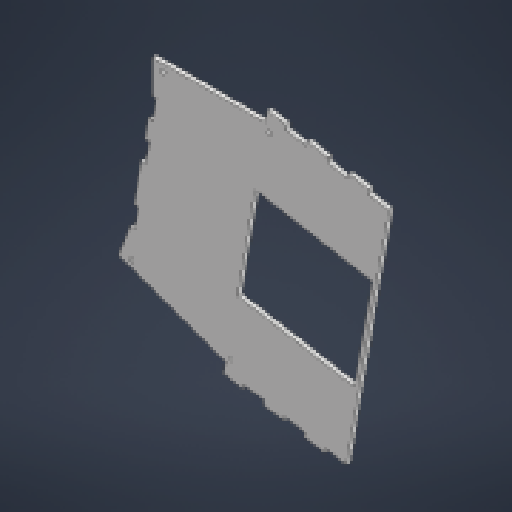
# Autodesk Inventor part: tapaderalateral
Saved by Autodesk Inventor 2027.1 (Build 311270010, 270A)
## iProperties
Created: 2026-10-11
Part Number: tapaderalateral
Material: Generic
Document SubType Name: Modeling
Designer: MineS
Density: 1 g/cm^3
Appearance: Default
Author: MineS
Autodesk Inventor part; units mm, degrees
ref_plane "YZ Plane" through (0, 0, 0) normal (1, 0, 0) x (0, 1, 0)
ref_plane "XZ Plane" through (0, 0, 0) normal (0, 1, 0) x (-1, 0, 0)
ref_plane "XY Plane" through (0, 0, 0) normal (0, 0, 1) x (1, 0, 0)
sketch "Sketch1" plane through (0, 0, 0) normal (0, 0, 1) x (1, 0, 0)
  line L0 (0, 0) -> (0, 24)
  line L1 (0, 24) -> (81.3777, 24)
  line L2 (81.3777, 24) -> (82.8537, 32.3709)
  line L3 (82.8537, 32.3709) -> (170.5618, 16.9056)
  line L4 (0, 0) -> (-15.6283, -88.6327)
  line L5 (-7.8142, -44.3163) -> (90.8416, -61.712)
  line L6 (90.8416, -61.712) -> (154.7135, -72.9744)
  line L7 (154.7135, -72.9744) -> (170.5618, 16.9056)
  line L8 (-15.6283, -88.6327) -> (-23.8368, -111.1853)
  line L9 (-23.8368, -111.1853) -> (52.6332, -139.0181)
  line L10 (52.6332, -139.0181) -> (51.1572, -147.389)
  line L11 (51.1572, -147.389) -> (138.8653, -162.8543)
  line L12 (154.7135, -72.9744) -> (138.8653, -162.8543)
  dimension "d1" = 24
  dimension "d2" = 100
  dimension "d3" = 90
  dimension "d25" = 8.5
  constraints: 26 end point, 4 symmetric about line, 3 perpendicular, 1 horizontal, 1 midpoint, 1 parallel, 1 vertical
  measures "d1" distance of L0.start L0.end
  measures "d2" angle of L1 L2
  measures "d3" distance of L0.start L4.end
  measures "d25" distance of L1.end L2.end
extrude "Extrusion1" add sketch "Sketch1" along normal blind 3.125
sketch "Sketch2" plane through (0, 0, 3.125) normal (0, 0, 1) x (1, 0, 0)
  circle A0 centre (8, 19) radius 1.45 projected
  circle A1 centre (84, 19) radius 1.45 projected
  line L0 (0, 0) -> (-15.6283, -88.6327) projected
  line L1 (-7.8142, -44.3163) -> (154.7135, -72.9744)
  line L2 (138.8653, -162.8543) -> (170.5618, 16.9056) projected
  circle A2 centre (-14.6092, -109.223) radius 1.45
  circle A3 centre (56.8075, -135.2165) radius 1.45
  circle A4 centre (8, 19) radius 1.5
  circle A5 centre (84, 19) radius 1.5
  circle A6 centre (56.8075, -135.2165) radius 1.5
  circle A7 centre (-14.6092, -109.223) radius 1.5
  dimension "d8" = 3
  dimension "d9" = 3
  dimension "d10" = 3
  dimension "d11" = 3
  constraints: 6 centre point, 4 coincident, 2 end point, 2 midpoint, 2 symmetric about line, 2 other
  measures "d8" diameter of A4
  measures "d9" diameter of A5
  measures "d10" diameter of A6
  measures "d11" diameter of A7
extrude "Extrusion3" cut sketch "Sketch2" against normal blind 3.125 contours A0 | A1 | A2 | A3 | A4 | A5 | A6 | A7
sketch "Sketch3" plane through (0, 0, 0) normal (0, 0, -1) x (-1, 0, 0)
  line L0 (-170.5618, 16.9056) -> (-82.8537, 32.3709) projected
  line L1 (-82.8537, 32.3709) -> (-82.3111, 29.2933)
  line L2 (-82.8537, 32.3709) -> (-81.3777, 24) projected
  line L3 (-82.3111, 29.2933) -> (-170.0192, 13.828)
  line L4 (-138.8653, -162.8543) -> (-170.5618, 16.9056) projected
  line L5 (-155.7897, 19.5103) -> (-155.247, 16.4328)
  line L6 (-141.0176, 22.115) -> (-140.4749, 19.0375)
  line L7 (-126.2455, 24.7197) -> (-125.7028, 21.6422)
  line L8 (-111.4733, 27.3245) -> (-110.9307, 24.2469)
  line L9 (-96.7012, 29.9292) -> (-96.1586, 26.8517)
  line L10 (0, 0) -> (15.6283, -88.6327) projected
  line L11 (7.8142, -44.3163) -> (-154.7135, -72.9744)
  line L12 (-138.8653, -162.8543) -> (-51.1572, -147.389)
  line L13 (-51.1572, -147.389) -> (-51.6999, -144.3115)
  line L14 (-51.1572, -147.389) -> (-52.6332, -139.0181)
  line L15 (-51.6999, -144.3115) -> (-139.4079, -159.7768)
  line L16 (-124.0932, -160.2496) -> (-124.6358, -157.1721)
  line L17 (-109.3211, -157.6449) -> (-109.8637, -154.5673)
  line L18 (-94.5489, -155.0401) -> (-95.0916, -151.9626)
  line L19 (-79.7768, -152.4354) -> (-80.3195, -149.3579)
  line L20 (-65.0047, -149.8307) -> (-65.5474, -146.7532)
  point P0 (-125.7028, 21.6422)
  point P1 (-126.2455, 24.7197)
  point P2 (-141.0176, 22.115)
  point P3 (-140.4749, 19.0375)
  point P4 (-96.7012, 29.9292)
  point P5 (-111.4733, 27.3245)
  point P6 (-110.9307, 24.2469)
  point P7 (-139.4079, -159.7768)
  point P8 (-109.3211, -157.6449)
  point P9 (-94.5489, -155.0401)
  point P10 (-65.5474, -146.7532)
  point P11 (-80.3195, -149.3579)
  point P12 (-79.7768, -152.4354)
  dimension "d14" = 3.125
  dimension "d15" = 15
  dimension "d18" = 15
  constraints: 34 end point, 14 symmetric about line, 7 point on line, 2 midpoint, 2 perpendicular, 13 other
  measures "d14" distance of L0.end L1.end
  measures "d15" distance between parallel lines of L4 L5
  measures "d18" distance of L5.start L6.start
extrude "Extrusion4" cut sketch "Sketch3" against normal blind 3.125 contours L15 L16 L12 L4 | L0 L5 L3 L4 | L0 L7 L3 L6 | L0 L9 L3 L8 | L15 L18 L12 L17 | L15 L20 L12 L19
sketch "Sketch4" plane through (0, 0, 3.125) normal (0, 0, 1) x (1, 0, 0)
  line L0 (139.4079, -159.7768) -> (170.0192, 13.828) projected
  line L1 (148.3754, -108.9199) -> (61.3922, -93.5824)
  line L2 (139.4079, -159.7768) -> (170.0192, 13.828) projected
  line L3 (61.3922, -93.5824) -> (74.0686, -21.6914)
  line L4 (0, 0) -> (-15.6283, -88.6327) projected
  line L5 (-7.8142, -44.3163) -> (154.7135, -72.9744)
  line L6 (74.0686, -21.6914) -> (161.0517, -37.0289)
  line L7 (145.2979, -108.3772) -> (157.9742, -36.4862)
  point P0 (67.7304, -57.6369)
  dimension "d26" = 88.325
  dimension "d27" = 73
  dimension "d28" = 3.125
  constraints: 10 end point, 5 point on line, 4 perpendicular, 3 midpoint
  measures "d26" distance of L1.start L1.end
  measures "d27" distance of L1.end L3.end
  measures "d28" distance between parallel lines of L0 L7
extrude "Extrusion5" cut sketch "Sketch4" against normal blind 10 contours L1 L3 L5 L7 | L5 L3 L6 L7
sketch "Sketch5" plane through (0, 0, 0) normal (0, 0, -1) x (-1, 0, 0)
  line L0 (0, 0) -> (15.6283, -88.6327) projected
  line L1 (0, 24) -> (0, 0) projected
  line L2 (15.6283, -88.6327) -> (0, 0)
  line L3 (0, 0) -> (-3.0775, -0.5427)
  line L4 (-3.0775, -0.5427) -> (12.5508, -89.1753)
  line L5 (12.5508, -89.1753) -> (15.6283, -88.6327)
  line L6 (2.6047, -14.7721) -> (-0.4728, -15.3148)
  line L7 (-3.5503, -15.8574) -> (-0.4728, -15.3148)
  line L8 (5.2094, -29.5442) -> (2.1319, -30.0869)
  line L9 (7.8142, -44.3163) -> (4.7366, -44.859)
  line L10 (10.4189, -59.0885) -> (7.3414, -59.6311)
  line L11 (13.0236, -73.8606) -> (9.9461, -74.4032)
  point P0 (0.342, -1.9397)
  point P1 (15.2635, -86.5636)
  point P2 (2.1319, -30.0869)
  dimension "d31" = 3.125
  dimension "d32" = 15
  dimension "d35" = 15
  constraints: 20 end point, 2 parallel, 2 perpendicular, 2 point on line, 1 symmetric about line, 13 other
  measures "d31" distance between parallel lines of L0 L4
  measures "d32" distance between parallel lines of L3 L6
  measures "d35" distance of L6.start L8.start
extrude "Extrusion6" cut sketch "Sketch5" against normal blind 10 contours L0 L6 L4 L3 | L0 L9 L4 L8 | L0 L5 L4 L11
body "Solid1"
